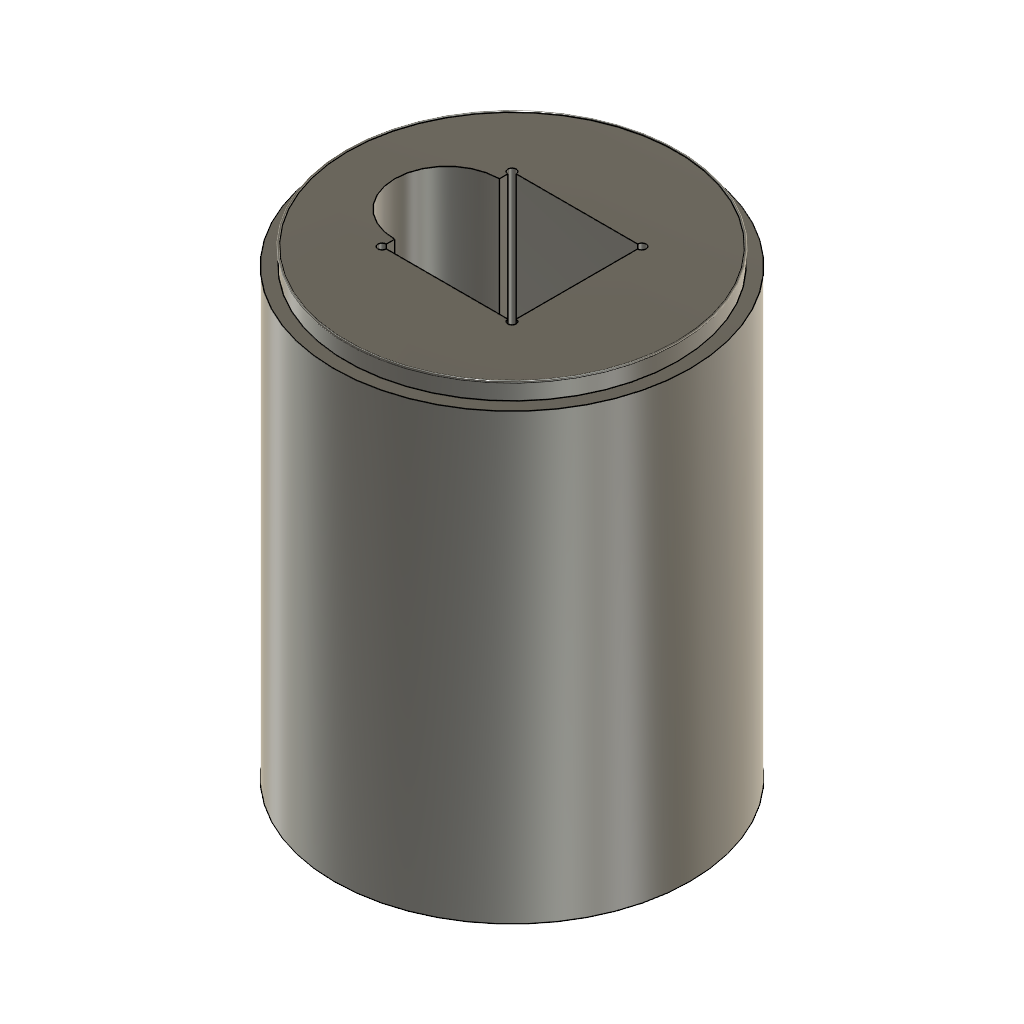
Kael_Rev1 (Autodesk Fusion 360 design; units mm, degrees)
Autodesk Fusion 360 part; units mm, degrees
sketch "Sketch1" plane through (0, 0, 0) normal (0, 0, 1) x (1, 0, 0)
  circle A0 centre (0, 0) radius 42.5
  dimension "d1" = 85
  constraint coincident A0.centre origin
  measures "d1" diameter of A0
extrude "Extrude1" add sketch "Sketch1" along normal blind 140 makes body 1
sketch "Sketch2" plane through (0, 0, 140) normal (0, 0, 1) x (-1, 0, 0)
  circle A0 centre (0, 0) radius 42.5
  line L0 (-15.5, -15.5) -> (15.5, -15.5)
  line L1 (15.5, -15.5) -> (15.5, 15.5)
  line L2 (15.5, 15.5) -> (-15.5, 15.5)
  line L3 (-15.5, 15.5) -> (-15.5, -15.5)
  line L4 (-15.5, -15.5) -> (15.5, 15.5) construction
  line L5 (15.5, -15.5) -> (-15.5, 15.5) construction
  dimension "d4" = 31
  dimension "d5" = 31
  constraint horizontal L0
  constraint perpendicular L0 L1
  constraint parallel L0 L2
  constraint parallel L1 L3
  constraint coincident L4 A0.centre
  constraint coincident L5 A0.centre
  constraint coincident A0.centre origin
  measures "d4" distance of L1.end L2.end
  measures "d5" distance of L0.end L1.end
extrude "Extrude2" cut sketch "Sketch2" against normal blind 144 contours L0 L1 L2 L3 bodies 1
sketch "Sketch3" plane through (0, 0, 140) normal (0, 0, 1) x (-1, 0, 0)
  line L0 (15.5, -15.5) -> (-15.5, -15.5)
  line L1 (-15.5, -15.5) -> (-15.5, 15.5)
  line L2 (-15.5, 15.5) -> (15.5, 15.5)
  line L3 (15.5, 15.5) -> (15.5, -15.5)
  circle A0 centre (0, 0) radius 42.5
  circle A1 centre (0, 0) radius 39.5
  dimension "d8" = 79
  constraint coincident A0.centre A1.centre
  measures "d8" diameter of A1
sketch "Sketch4" plane through (0, 0, 140) normal (0, 0, 1) x (-1, 0, 0)
extrude "Extrude3" add sketch "Sketch3" along normal blind 4 contours A1 bodies 1
sketch "Sketch5" plane through (0, 0, 144) normal (0, 0, 1) x (-1, 0, 0)
  line L0 (-15.5, 15.5) -> (15.5, 15.5)
  line L1 (15.5, 15.5) -> (15.5, -15.5)
  line L2 (15.5, -15.5) -> (-15.5, -15.5)
  line L3 (-15.5, -15.5) -> (-15.5, 15.5)
  circle A0 centre (0, 0) radius 39.5
  circle A1 centre (15.5, 0) radius 12.5
  dimension "d11" = 25
  constraint midpoint L1 A1.centre
  measures "d11" diameter of A1
extrude "Extrude5" cut sketch "Sketch5" against normal blind 144 contours L1 A1 picked at (20.5525, 3.4831) bodies 1
sketch "Sketch6" plane through (0, 0, 144) normal (0, 0, 1) x (-1, 0, 0)
  circle A0 centre (-15.5, 15.5) radius 1
  circle A1 centre (-15.5, -15.5) radius 1
  circle A2 centre (15.5, -15.5) radius 1
  circle A3 centre (15.5, 15.5) radius 1
  dimension "d16" = 2
  dimension "d18" = 360
  dimension "d19" = 15.5
  dimension "d20" = 15.5
  measures "d16" diameter of A0
  measures "d19" horizontal distance of origin A0.centre
  measures "d20" vertical distance of origin A0.centre
extrude "Extrude6" cut sketch "Sketch6" against normal blind 144 bodies 1
pipe "Pipe1" add diameter 0.5 path "Sketch5" along A0 bodies 1
ref_plane "WorkPlane1" through (0, 0, 34) normal (0, 0, 1) x (1, 0, 0)
split "Split1" by plane through (0, 0, 34) normal (0, 0, 1) bodies 1 makes body 2 at (42.2888, 4.2316, 69.3333)
hidden bodies 1
